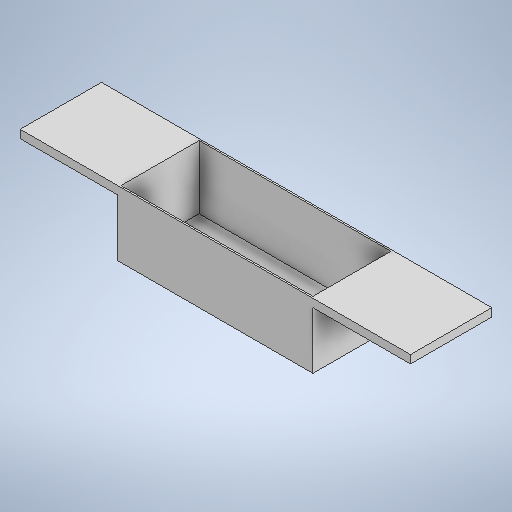
# Autodesk Inventor part: Support
Saved by Autodesk Inventor 2025.1 (Build 291241000, 241)
## iProperties
Created: 2025-06-05
Part Number: Support
Material: Generic
Document SubType Name: Modeling
Designer: Lenovo
Density: 1 g/cm^3
Appearance: Default
Author: Lenovo
Autodesk Inventor part; units mm, degrees
ref_plane "YZ Plane" through (0, 0, 0) normal (1, 0, 0) x (0, 1, 0)
ref_plane "XZ Plane" through (0, 0, 0) normal (0, 1, 0) x (-1, 0, 0)
ref_plane "XY Plane" through (0, 0, 0) normal (0, 0, 1) x (1, 0, 0)
sketch "Sketch1" plane through (0, 0, 0) normal (0, 0, 1) x (1, 0, 0)
  line L0 (0, 0) -> (120, 0)
  line L1 (120, 0) -> (120, 40)
  line L2 (120, 40) -> (0, 40)
  line L3 (0, 40) -> (0, 0)
  dimension "d0" = 120
  dimension "d1" = 40
  constraints: 8 end point, 2 parallel, 1 horizontal, 1 perpendicular
  measures "d0" distance of L2.end L1.end
  measures "d1" distance of L1.end L0.end
extrude "Extrusion1" add sketch "Sketch1" along normal mid plane 50
sketch "Sketch2" plane through (0, 40, 25) normal (0, 1, 0) x (1, 0, 0)
  line L0 (0, 50) -> (0, 0) projected
  line L1 (0, 50) -> (-70, 50)
  line L2 (-70, 50) -> (-70, 0)
  line L3 (-70, 0) -> (0, 0)
  line L4 (0, 0) -> (0, 50)
  line L5 (120, 50) -> (120, 0) projected
  line L6 (120, 0) -> (190, 0)
  line L7 (190, 0) -> (190, 50)
  line L8 (190, 50) -> (120, 50)
  line L9 (120, 50) -> (120, 0)
  line L10 (1, 1) -> (119, 1)
  line L11 (119, 1) -> (119, 49)
  line L12 (119, 49) -> (1, 49)
  line L13 (1, 49) -> (1, 1)
  point P0 (0, 25)
  dimension "d4" = 70
  dimension "d5" = 70
  dimension "d6" = 50
  dimension "d7" = 118
  dimension "d8" = 48
  constraints: 24 end point, 6 parallel, 3 horizontal, 3 perpendicular
  measures "d4" distance of L3.end L2.end
  measures "d5" distance of L8.end L7.end
  measures "d6" distance of L7.end L6.end
  measures "d7" distance of L12.end L11.end
  measures "d8" distance of L11.end L10.end
extrude "Extrusion2" cut sketch "Sketch2" against normal blind 39 contours L13 L12 L11 L10
sketch "Sketch3" plane through (0, 40, 25) normal (0, 1, 0) x (1, 0, 0)
  line L0 (0, 50) -> (120, 50) projected
  line L1 (0, 50) -> (-70, 50)
  line L2 (-70, 50) -> (-70, 0)
  line L3 (-70, 0) -> (0, 0)
  line L4 (0, 0) -> (0, 50)
  line L5 (120, 50) -> (190, 50)
  line L6 (190, 50) -> (190, 0)
  line L7 (190, 0) -> (120, 0)
  line L8 (120, 0) -> (120, 50)
  point P0 (0, 25)
  dimension "d11" = 70
  dimension "d12" = 50
  dimension "d13" = 70
  dimension "d14" = 50
  constraints: 16 end point, 4 parallel, 2 horizontal, 2 perpendicular
  measures "d11" distance of L3.end L2.end
  measures "d12" distance of L2.end L1.end
  measures "d13" distance of L6.end L7.end
  measures "d14" distance of L5.end L6.end
extrude "Extrusion3" add sketch "Sketch3" against normal blind 5
sketch "Sketch6" plane through (0, 0, 25) normal (0, -1, 0) x (1, 0, 0)
  line L0 (10, -32) -> (110, -32)
  line L1 (110, -32) -> (110, -30)
  line L2 (110, -30) -> (10, -30)
  line L3 (10, -30) -> (10, -32)
  line L4 (10, -20) -> (110, -20)
  line L5 (110, -20) -> (110, -18)
  line L6 (110, -18) -> (10, -18)
  line L7 (10, -18) -> (10, -20)
  point P0 (0, -25)
  dimension "d17" = 100
  dimension "d18" = 2
  dimension "d19" = 100
  dimension "d20" = 2
  constraints: 16 end point, 4 parallel, 2 horizontal, 2 perpendicular
  measures "d17" distance of L2.end L1.end
  measures "d18" distance of L1.end L0.end
  measures "d19" distance of L6.end L5.end
  measures "d20" distance of L5.end L4.end
extrude "Extrusion4" cut sketch "Sketch6" against normal blind 5
sketch "Sketch7" plane through (-70, 40, 25) normal (0, 1, 0) x (1, 0, 0)
  line L0 (0, 0) -> (0, 50) projected
  line L1 (0, 0) -> (260, 0) projected
  line L2 (0, 50) -> (10, 50)
  line L3 (10, 50) -> (10, 0)
  line L4 (10, 0) -> (0, 0)
  line L5 (0, 0) -> (0, 50)
  line L6 (260, 50) -> (0, 50) projected
  line L7 (260, 50) -> (250, 50)
  line L8 (250, 50) -> (250, 0)
  line L9 (250, 0) -> (260, 0)
  line L10 (260, 0) -> (260, 50)
  point P0 (70, 25)
  dimension "d23" = 10
  dimension "d24" = 10
  constraints: 16 end point, 4 parallel, 2 horizontal, 2 perpendicular, 2 point on line
  measures "d23" distance of L3.end L4.end
  measures "d24" distance of L9.end L8.end
extrude "Extrusion5" cut sketch "Sketch7" against normal blind 10 contours L0 L2 L3 L1 | L8 L6 L10 L1
body "Solid1"
